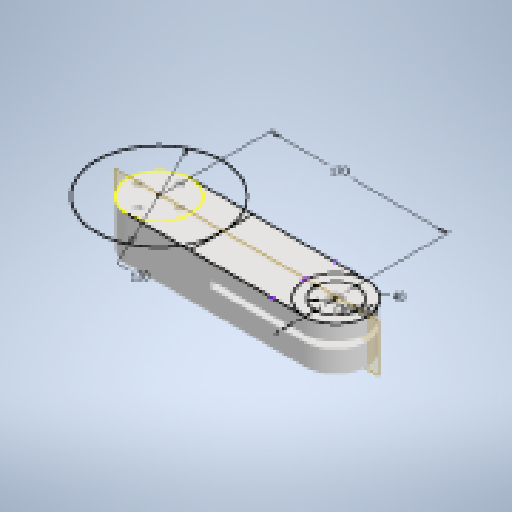
# Autodesk Inventor part: плечо r1
Saved by Autodesk Inventor 2024.2 (Build 282272000, 272)
## iProperties
Created: 2026-10-20
Part Number: плечо r1
Material: Типовые
Document SubType Name: Modeling
Designer: katya_notebook
Density: 1 g/cm^3
Appearance: По умолчанию
Author: katya_notebook
Autodesk Inventor part; units mm, degrees
ref_plane "YZ Plane" through (0, 0, 0) normal (1, 0, 0) x (0, 1, 0)
ref_plane "XZ Plane" through (0, 0, 0) normal (0, 1, 0) x (-1, 0, 0)
sketch "Эскиз1" plane through (0, 0, 0) normal (0, 1, 0) x (-1, 0, 0)
  circle A0 centre (0, 0) radius 30
  circle A1 centre (0, 0) radius 20
  circle A2 centre (20, 0) radius 1.6
  circle A3 centre (0, -20) radius 1.6
  circle A4 centre (-20, 0) radius 1.6
  circle A5 centre (0, 20) radius 1.6
  line L0 (0, 0) -> (48.5011, 0) construction
  dimension "d1" = 40
  dimension "d0" = 60
  dimension "d2" = 3.2
  dimension "d5" = 360
  constraints: 5 centre point, 2 coincident, 2 end point, 1 horizontal, 1 horizontal alignment, 1 point on line, 11 other
  measures "d0" diameter of A0
  measures "d2" diameter of A2
extrude "Выдавливание1" add sketch "Эскиз1" along normal blind 42 contours A0 | A2 A1 A3 A4 A5
sketch "Эскиз3" plane through (0, 42, 0) normal (0, 1, 0) x (1, 0, 0)
  circle A0 centre (0, 0) radius 30 projected
  line L0 (0, -30) -> (170, -30)
  circle A1 centre (170, 0) radius 30
  circle A2 centre (0, 0) radius 30 projected
  line L1 (0, 30) -> (170, 30)
  circle A3 centre (170, 0) radius 20
  line L2 (190, 0) -> (190, 0)
  circle A4 centre (190, 0) radius 1.6
  circle A5 centre (170, 20) radius 1.6
  circle A6 centre (150, 0) radius 1.6
  circle A7 centre (170, -20) radius 1.6
  line L3 (170, 0) -> (170, -59.0667)
  circle A8 centre (0, 0) radius 60
  line L4 (60, 30) -> (60, -30)
  point P0 (140.0494, 1.7204)
  point P1 (140.0494, -1.7204)
  point P2 (171.5987, -19.936)
  point P3 (168.4013, -19.936)
  point P4 (150.064, -1.5987)
  point P5 (150.064, 1.5987)
  point P6 (168.4013, 19.936)
  point P7 (171.5987, 19.936)
  point P8 (189.936, 1.5987)
  point P9 (189.936, -1.5987)
  point P10 (189.8848, -0.5431)
  point P11 (140, -30)
  point P12 (140, 30)
  point P13 (140, 0)
  point P14 (51.9615, 30)
  point P15 (51.9615, -30)
  point P16 (60, 0)
  dimension "d47" = 120
  dimension "d12" = 170
  dimension "d13" = 40
  dimension "d14" = 3.2
  dimension "d17" = 360
  constraints: 10 end point, 8 point on circle, 6 centre point, 5 point on line, 4 horizontal, 3 coincident, 2 vertical, 1 equal radius, 1 midpoint, 1 perpendicular, 1 tangent, 14 other
  measures "d12" distance of point (0, 0) A1.centre
  measures "d13" diameter of A3
  measures "d14" diameter of A4
extrude "Выдавливание3" add sketch "Эскиз3" against normal blind 42 contours A0 L1 A8 L0 | L1 L4 A8 | A8 L4 L0 | L1 A1 L0 L4 | A7 A3 L3 | L3 A3 A7 | A1 | A7 L3 A3 | A3 A6 A5 A4 A7 | L3 A7 A3 | A6 A3 | A3 A6 | A4 A3 | A3 A4 | A5 A3 | A3 A5 picked at (49.6962, 3.473)
sketch "Эскиз2" plane through (0, 42, 0) normal (0, 1, 0) x (1, 0, 0)
  circle A0 centre (-20, 0) radius 1.6 projected
  circle A1 centre (-20, 0) radius 4
  circle A2 centre (0, 20) radius 1.6 projected
  circle A3 centre (0, 20) radius 4
  circle A4 centre (20, 0) radius 1.6 projected
  circle A5 centre (20, 0) radius 4
  circle A6 centre (0, -20) radius 1.6 projected
  circle A7 centre (0, -20) radius 4
  line L0 (0, 30) -> (170, 30) projected
  line L1 (30, 30) -> (30, -30)
  line L2 (170, -30) -> (0, -30) projected
  point P0 (0, 0)
  point P1 (140, 30)
  point P2 (140, -30)
  point P3 (60, 30)
  point P4 (60, -30)
  dimension "d9" = 8
  constraints: 4 centre point, 4 coincident, 3 equal radius, 2 end point, 2 point on line
  measures "d9" diameter of A3
extrude "Выдавливание2" cut sketch "Эскиз2" against normal blind 4 contours A1 | A2 | A3 | A5 | A7
sketch "Эскиз5" plane through (0, 42, 0) normal (0, 1, 0) x (1, 0, 0)
  circle A0 centre (170, 0) radius 7
  point P0 (0, 0)
  dimension "d26" = 14
  dimension "d27" = 170
  constraints: 1 centre point
  measures "d26" diameter of A0
  measures "d27" distance of A0.centre point (0, 0)
extrude "Выдавливание5" cut sketch "Эскиз5" against normal blind 5
sketch "Эскиз6" plane through (170, 37, 0) normal (0, 1, 0) x (1, 0, 0)
  circle A0 centre (0, 0) radius 3.75
  point P0 (-170, 0)
  dimension "d30" = 7.5
  constraints: 1 centre point
  measures "d30" diameter of A0
extrude "Выдавливание6" cut sketch "Эскиз6" against normal blind 5
sketch "Эскиз7" plane through (170, 32, 0) normal (0, 1, 0) x (1, 0, 0)
  point P0 (-170, 0)
sketch "Эскиз8" plane through (170, 32, 0) normal (0, 1, 0) x (1, 0, 0)
  circle A0 centre (0, 0) radius 12.95
  point P0 (-170, 0)
  dimension "d33" = 25.9
  constraints: 1 centre point
  measures "d33" diameter of A0
extrude "Выдавливание7" cut sketch "Эскиз8" against normal blind 5
sketch "Эскиз9" plane through (170, 27, 0) normal (0, 1, 0) x (1, 0, 0)
  circle A0 centre (0, 0) radius 6.25
  point P0 (-170, 0)
  dimension "d36" = 12.5
  constraints: 1 centre point
  measures "d36" diameter of A0
extrude "Выдавливание8" cut sketch "Эскиз9" against normal blind 4.7
sketch "Эскиз10" plane through (170, 22.3, 0) normal (0, 1, 0) x (1, 0, 0)
  line L0 (-26.2827, 5.3349) -> (81.116, 5.3349) construction
  circle A0 centre (0, 0) radius 20.25
  line L1 (-20.25, 0) -> (-20.25, 87.7521)
  line L2 (-20.25, 0) -> (67.5021, 0) construction
  line L3 (-20.25, 87.7521) -> (70.2326, -20.25)
  line L4 (-20.25, 0) -> (-20.25, -79.175)
  line L5 (-20.25, -79.175) -> (70.2326, -20.25)
  line L6 (-20.25, -79.175) -> (-90.25, -79.175)
  line L7 (-90.25, -79.175) -> (-90.25, 87.7521)
  line L8 (-90.25, 87.7521) -> (-20.25, 87.7521)
  line L9 (-20.25, 87.7521) -> (-20.25, -79.175)
  point P0 (-170, 0)
  point P1 (0, -20.25)
  point P2 (-20.25, 87.7521)
  dimension "d41" = 40.5
  dimension "d42" = 90
  dimension "d48" = 70
  constraints: 20 end point, 3 horizontal, 2 parallel, 2 perpendicular, 2 point on circle, 2 tangent, 1 centre point, 1 point on line
  measures "d41" diameter of A0
  measures "d42" angle of L2 L1
  measures "d48" distance of L7.end L8.end
extrude "Выдавливание9" cut sketch "Эскиз10" along normal blind 4.7 and the other way blind 1.8 contours A0 | L1 L3 L5 L4 | L4 L6 L7 L8 L1
sketch "Эскиз12" plane through (0, 0, 0) normal (0, -1, 0) x (1, 0, 0)
  circle A0 centre (170, 0) radius 7
  point P0 (0, 0)
  dimension "d49" = 170
  dimension "d50" = 14
  constraints: 1 centre point
  measures "d49" distance of A0.centre point (0, 0)
  measures "d50" diameter of A0
extrude "Выдавливание10" cut sketch "Эскиз12" against normal blind 5.5
sketch "Эскиз13" plane through (170, 5.5, 0) normal (0, -1, 0) x (1, 0, 0)
  circle A0 centre (0, 0) radius 3.5
  point P0 (-170, 0)
  dimension "d53" = 7
  constraints: 1 centre point
  measures "d53" diameter of A0
extrude "Выдавливание11" cut sketch "Эскиз13" against normal blind 10
